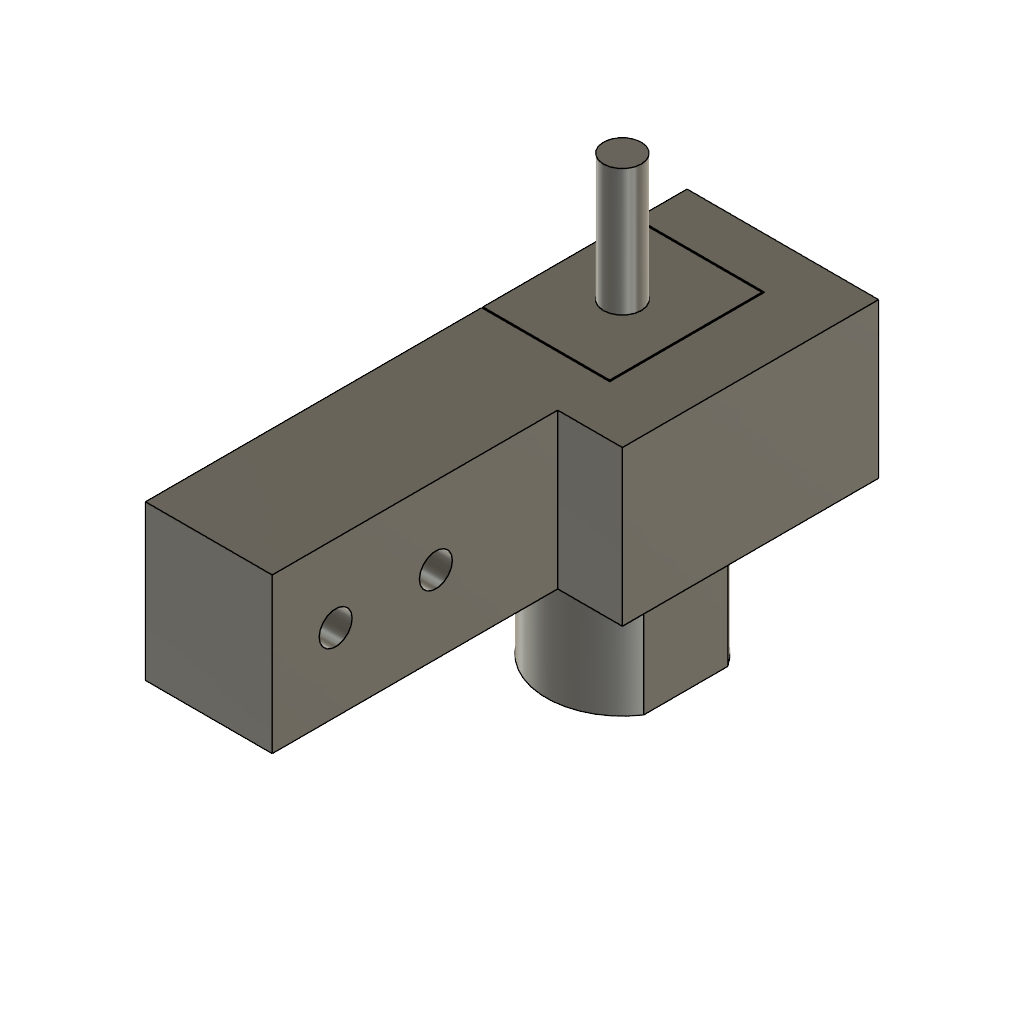
DC_Motor_And_Connector (Autodesk Fusion 360 design; units mm, degrees)
description: Spur Gear; Module: 1.4; Num Teeth: 10; Pressure Angle: 20.0; Backlash: 0.00 mm
Autodesk Fusion 360 part; units mm, degrees
sketch "Çizim1" plane through (0, 0, 0) normal (0, 0, 1) x (1, 0, 0)
  line L0 (5, 6) -> (-5, 6)
  line L1 (-5, 6) -> (-5, -6)
  line L2 (-5, -6) -> (5, -6)
  line L3 (5, -6) -> (5, 6)
  line L4 (5, 6) -> (-5, -6) construction
  line L5 (-5, 6) -> (5, -6) construction
  dimension "d1" = 10
  dimension "d2" = 12
  constraint horizontal L0
  constraint perpendicular L0 L1
  constraint parallel L0 L2
  constraint parallel L1 L3
  constraint coincident L4 origin
  constraint coincident L5 origin
  measures "d1" distance of L1.end L2.end
  measures "d2" distance of L0.end L1.end
extrude "Ekstrüzyon1" add sketch "Çizim1" along normal blind 24.2 makes body 1
sketch "Çizim2" plane through (0, 0, 24.2) normal (0, 0, 1) x (-1, 0, 0)
  line L0 (-5, 6) -> (-5, -6)
  line L1 (-5, -6) -> (5, -6)
  line L2 (5, -6) -> (5, 6)
  line L3 (5, 6) -> (-5, 6)
  circle A0 centre (0, 0) radius 1.5
  dimension "d5" = 3
  constraint coincident A0.centre origin
  measures "d5" diameter of A0
extrude "Ekstrüzyon2" add sketch "Çizim2" along normal blind 10 contours A0 bodies 1
sketch "Çizim3" plane through (0, 0, 0) normal (0, 0, -1) x (1, 0, 0)
  line L0 (5, -6) -> (5, 6)
  line L1 (5, 6) -> (-5, 6)
  line L2 (-5, 6) -> (-5, -6)
  line L3 (-5, -6) -> (5, -6)
  circle A0 centre (0, 0) radius 2.5
  dimension "d8" = 5
  constraint coincident A0.centre origin
  measures "d8" diameter of A0
extrude "Ekstrüzyon3" add sketch "Çizim3" along normal blind 1 contours A0 bodies 1
sketch "Çizim4" plane through (0, 0, 0) normal (0, 0, -1) x (1, 0, 0)
  circle A0 centre (0, 0) radius 2.5
  line L0 (5, -6) -> (5, 6)
  line L1 (5, 6) -> (-5, 6)
  line L2 (-5, 6) -> (-5, -6)
  line L3 (-5, -6) -> (5, -6)
  circle A1 centre (0, 0) radius 6
  dimension "d11" = 12
  constraint coincident A0.centre A1.centre
  measures "d11" diameter of A1
extrude "Ekstrüzyon4" cut sketch "Çizim4" against normal blind 12 contours L0 L3 A1 | L2 L3 A1 | L0 L1 A1 | L1 L2 A1 bodies 1
sketch "Çizim28" plane through (0, 0, 24.2) normal (0, 0, 1) x (-1, 0, 0)
  circle A0 centre (0, 0) radius 1.5
  line L0 (-5, 6) -> (-5, -6)
  line L1 (-5, -6) -> (5, -6)
  line L2 (5, -6) -> (5, 6)
  line L3 (5, 6) -> (-5, 6)
  line L4 (5, -6) -> (-5, -6)
  line L5 (-5, -6) -> (-5, 6)
  line L6 (-5, 6) -> (5, 6)
  line L7 (5, 6) -> (5, -6)
  line L8 (5.1, -6.1) -> (-5.1, -6.1)
  line L9 (-5.1, -6.1) -> (-5.1, 6.1)
  line L10 (-5.1, 6.1) -> (5.1, 6.1)
  line L11 (5.1, 6.1) -> (5.1, -6.1)
  line L12 (5, 6) -> (5, 6.1)
  line L13 (5, -6) -> (5, -6.1)
  line L14 (5, -6.1) -> (5, -12.1)
  line L15 (5, 6.1) -> (5, 12.1)
  line L16 (5, -12.1) -> (-5, -12.1)
  line L17 (-5, -12.1) -> (-5, -8.1)
  line L18 (5.1, 0) -> (-5.1, 0) construction
  line L19 (-5.1, -6.1) -> (-10.1, -6.1)
  line L20 (-10.1, -6.1) -> (-10.1, -8.1)
  line L21 (-5, -8.1) -> (-10.1, -8.1)
  line L22 (-5.1, 0) -> (-10.1, 0)
  line L23 (-10.1, 0) -> (-10.1, -6.1)
  line L24 (-10.1, 0) -> (-10.1, 6.1)
  line L25 (-10.1, 6.1) -> (-10.1, 8.1)
  line L26 (-5, 8.1) -> (-10.1, 8.1)
  line L27 (-5, 12.1) -> (-5, 8.1)
  line L28 (5, 12.1) -> (-5, 12.1)
  line L29 (5, 6.1) -> (5, 12.1)
  dimension "d90" = -0.1
  dimension "d91" = 6
  dimension "d92" = 6
  dimension "d93" = 4
  dimension "d94" = 10
  dimension "d95" = 5
  constraint horizontal L4
  constraint vertical L5
  constraint horizontal L6
  constraint vertical L7
  constraint coincident L0.start L3.end
  constraint coincident L1.end L2.start
  constraint coincident L10 L12.end
  constraint perpendicular L10 L12
  constraint coincident L8 L13.end
  constraint perpendicular L8 L13
  constraint perpendicular L8 L14
  constraint perpendicular L10 L15
  constraint perpendicular L14 L16
  constraint perpendicular L8 L17
  constraint midpoint L11 L18.start
  constraint midpoint L9 L18.end
  constraint perpendicular L9 L19
  constraint perpendicular L19 L20
  constraint perpendicular L20 L21
  constraint perpendicular L9 L22
  constraint perpendicular L19 L23
  constraint symmetric L13.end L18 L12.end
  constraint symmetric L14.end L18 L15.end
  constraint symmetric L16.end L18 L27.start
  constraint symmetric L17.end L18 L26.start
  constraint symmetric L18 L19.end L24.end
  constraint symmetric L18 L20.end L25.end
  constraint symmetric L18 L22.end L23.start
  measures "d91" distance of L13.end L14.end
  measures "d92" distance of L12.end L15.end
  measures "d93" distance of L16.end L17.end
  measures "d94" distance of L14.end L16.end
  measures "d95" distance of L8.end L19.end
extrude "Ekstrüzyon29" add sketch "Çizim28" against normal blind 12.2 separate body contours L9 L10 L15 L22 L24 L25 L26 L27 L28 L29 | L8 L14 L16 L17 L19 L20 L21 | L9 L19 L22 L23 makes body 2
extrude "Ekstrüzyon30" add 1 faces at (-1.6667, -12.1, 16.0667) along direction (0, -1, 0) blind 3 on bodies 2 bodies 2
extrude "Ekstrüzyon31" add 1 faces at (-1.6667, 12.1, 16.0667) along direction (0, 1, 0) blind 3 on bodies 2 bodies 2
sketch "Çizim29" plane through (5, 0, 0) normal (1, 0, 0) x (0, 1, 0)
  line L0 (-8.1, 24.2) -> (-15.1, 24.2)
  line L1 (-15.1, 24.2) -> (-15.1, 12)
  line L2 (-15.1, 12) -> (-8.1, 12)
  line L3 (-8.1, 12) -> (-8.1, 24.2)
  line L4 (-13.7, 12) -> (-13.7, 24.2)
  line L5 (-15.1, 18.1) -> (-8.1, 18.1)
  circle A0 centre (-13.7, 18.1) radius 1.3
  dimension "d102" = 2.6
  dimension "d121" = 1.4
  constraint midpoint L1 L5.start
  constraint midpoint L3 L5.end
  constraint midpoint L4 A0.centre
  measures "d102" diameter of A0
  measures "d121" distance of L1 L4
extrude "Ekstrüzyon32" cut sketch "Çizim29" against normal blind 10 contours L4 L5 A0 | L4 L5 A0 | L4 L5 A0 | L4 L5 A0 bodies 2
extrude "Ekstrüzyon33" cut 1 faces at (5, 12.7667, 16.0667) along direction (-1, 0, 0) blind 10 on bodies 2 bodies 2
extrude "Ekstrüzyon34" add 1 faces at (0.0333, 8.1, 16.0667) along direction (0, 1, 0) blind 2 on bodies 2 bodies 2
extrude "Ekstrüzyon35" add 1 faces at (-1.6667, -15.1, 16.0667) along direction (0, -1, 0) blind 10 on bodies 2 bodies 2
sketch "Çizim30" plane through (5, 0, 0) normal (1, 0, 0) x (0, 1, 0)
  circle A0 centre (-13.7, 18.1) radius 1.3
  line L0 (-8.1, 24.2) -> (-25.1, 24.2)
  line L1 (-25.1, 24.2) -> (-25.1, 12)
  line L2 (-25.1, 12) -> (-8.1, 12)
  line L3 (-8.1, 12) -> (-8.1, 24.2)
  line L4 (-16.6, 24.2) -> (-16.6, 12)
  circle A1 centre (-21.6, 18.1) radius 1.3
  dimension "d111" = 2.6
  dimension "d112" = 5
  dimension "d113" = 6.1
  constraint midpoint L0 L4.start
  constraint midpoint L2 L4.end
  measures "d111" diameter of A1
  measures "d112" distance of L4 A1.centre
  measures "d113" distance of L2 A1.centre
extrude "Ekstrüzyon36" cut sketch "Çizim30" against normal blind 10 contours A1 bodies 2
extrude "Ekstrüzyon37" add 1 faces at (-1.6667, -25.1, 16.0667) along direction (0, -1, 0) blind 1.5 on bodies 2 bodies 2
extrude "Ekstrüzyon38" add 1 faces at (6.7, -8.1, 20.1333) along direction (0, -1, 0) blind 2 on bodies 2 bodies 2
sketch "Çizim32" plane through (-5, 0, 0) normal (-1, 0, 0) x (0, -1, 0)
  circle A0 centre (21.6, 18.1) radius 1.3
  circle A1 centre (13.7, 18.1) radius 1.3
  line L0 (26.6, 24.2) -> (6.1, 24.2)
  line L1 (6.1, 24.2) -> (6.1, 12)
  line L2 (6.1, 12) -> (26.6, 12)
  line L3 (26.6, 12) -> (26.6, 24.2)
  line L4 (26.6, 24.2) -> (6.1, 24.2)
  line L5 (6.1, 24.2) -> (6.1, 12)
  line L6 (6.1, 12) -> (26.6, 12)
  line L7 (26.6, 12) -> (26.6, 24.2)
  circle A2 centre (21.6, 18.1) radius 1.3
  circle A3 centre (13.7, 18.1) radius 1.3
  line L8 (26.6, 24.2) -> (32.6, 24.2)
  line L9 (32.6, 24.2) -> (32.6, 12)
  line L10 (32.6, 12) -> (26.6, 12)
  line L11 (26.6, 12) -> (26.6, 24.2)
  circle A4 centre (27.6, 18.1) radius 1.3
  dimension "d122" = 6
  dimension "d123" = 12.2
  dimension "d124" = 2.6
  dimension "d125" = 5
  dimension "d126" = 6.1
  constraint horizontal L4
  constraint vertical L5
  constraint horizontal L6
  constraint vertical L7
  constraint coincident L1.end L2.start
  constraint coincident L0.start L3.end
  constraint concentric A0 A2
  constraint concentric A1 A3
  constraint horizontal L8
  constraint vertical L9
  constraint horizontal L10
  constraint vertical L11
  measures "d122" distance of L0.start L8.end
  measures "d123" distance of L0.start L2.end
  measures "d124" diameter of A4
  measures "d125" distance of L9 A4.centre
  measures "d126" distance of L10 A4.centre
extrude "Ekstrüzyon39" add sketch "Çizim32" against normal blind 10 contours A0 A2 | A1 A3 | L3 L7 L8 L9 L10 L11 A4 | L3 L7 L11 A4 picked at (26.5, 18.1) bodies 2
sketch "Çizim33" plane through (5, 0, 0) normal (1, 0, 0) x (0, 1, 0)
  line L0 (-26.6, 18.9307) -> (-26.6, 17.2693)
  arc A0 (-26.6, 18.9307) -> (-26.6, 17.2693) centre (-27.6, 18.1) ccw
  line L1 (-10.1, 24.2) -> (-32.6, 24.2)
  line L2 (-32.6, 24.2) -> (-32.6, 12)
  line L3 (-32.6, 12) -> (-10.1, 12)
  line L4 (-10.1, 12) -> (-10.1, 24.2)
  circle A1 centre (-27.6, 18.1) radius 1.3
  line L5 (-27.6, 18.1) -> (-19.7, 18.1)
  circle A2 centre (-19.7, 18.1) radius 1.3
  dimension "d129" = 2.6
  dimension "d130" = 7.9
  dimension "d131" = 2.6
  constraint concentric A0 A1
  constraint coincident A0.centre A1.centre
  constraint perpendicular L0 L5
  constraint coincident L5.end A2.centre
  measures "d129" diameter of A1
  measures "d130" distance of A0.centre L5.end
  measures "d131" diameter of A2
extrude "Ekstrüzyon40" cut sketch "Çizim33" against normal blind 10 contours L0 A1 L5 | L0 A1 L5 | A2 bodies 2
equation "d113 = ( 12.2 / 2 ) * 1 mm"
equation "d126 = ( 12.2 / 2 ) * 1 mm"
